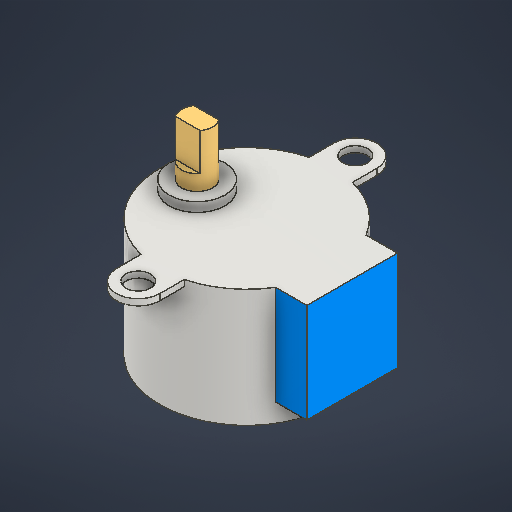
# Autodesk Inventor part: 28BJY-48
Saved by Autodesk Inventor 2026.2 (Build 302298010, 298A)
## iProperties
Created: 2026-05-01
Part Number: 28BJY-48
Material: 강철, 가공됨
Document SubType Name: Modeling
Designer: work
Density: 7.85 g/cm^3
Appearance: 강철
Author: work
Autodesk Inventor part; units mm, degrees
ref_plane "YZ Plane" through (0, 0, 0) normal (1, 0, 0) x (0, 1, 0)
ref_plane "XZ Plane" through (0, 0, 0) normal (0, 1, 0) x (-1, 0, 0)
ref_plane "XY Plane" through (0, 0, 0) normal (0, 0, 1) x (1, 0, 0)
sketch "스케치1" plane through (0, 0, 0) normal (0, 1, 0) x (-1, 0, 0)
  circle A0 centre (0, 0) radius 14
  line L0 (0, 7.3) -> (-17, 7.3)
  line L1 (-17, 7.3) -> (-17, -7.3)
  line L2 (-17, -7.3) -> (0, -7.3)
  line L3 (0, -7.3) -> (0, 7.3)
  point P0 (-11.9461, -7.3)
  point P1 (-11.9461, 7.3)
  dimension "d0" = 28
  dimension "d1" = 14.6
  dimension "d2" = 17
  constraints: 8 end point, 2 coincident, 2 parallel, 1 centre point, 1 horizontal, 1 midpoint, 1 perpendicular
  measures "d0" diameter of A0
  measures "d1" distance of L0.end L1.end
  measures "d2" distance of L1.end L2.end
extrude "돌출1" add sketch "스케치1" along normal blind 19
sketch "스케치2" plane through (0, 19, 0) normal (0, 1, 0) x (1, 0, 0)
  line L0 (0, 0) -> (-8, 0) construction
  circle A0 centre (-8, 0) radius 4.5
  line L1 (0, -17.5) -> (0, 17.5) construction
  line L2 (3.5, -17.5) -> (3.5, 17.5)
  line L3 (-3.5, 17.5) -> (-3.5, -17.5)
  arc A1 (-3.5, -17.5) -> (3.5, -17.5) centre (0, -17.5) ccw
  arc A2 (3.5, 17.5) -> (-3.5, 17.5) centre (0, 17.5) ccw
  circle A3 centre (0, 17.5) radius 2
  circle A4 centre (0, -17.5) radius 2
  line L4 (11.9461, -7.3) -> (17, -7.3) projected
  line L5 (17, -7.3) -> (17, 7.3) projected
  line L6 (17, 7.3) -> (11.9461, 7.3) projected
  arc A5 (11.9461, 7.3) -> (11.9461, -7.3) centre (0, 0) ccw projected
  point P0 (3.5, 13.5554)
  point P1 (3.5, -13.5554)
  point P2 (-3.5, 13.5554)
  point P3 (-3.5, -13.5554)
  dimension "d5" = 8
  dimension "d6" = 9
  dimension "d7" = 35
  dimension "d8" = 7
  dimension "d9" = 4
  dimension "d10" = 4
  constraints: 10 end point, 5 centre point, 4 point on circle, 4 tangent, 3 coincident, 1 horizontal, 1 midpoint, 1 parallel, 1 vertical
  measures "d5" distance of L0.start L0.end
  measures "d6" diameter of A0
  measures "d7" distance of L1.start L1.end
  measures "d8" distance between parallel lines of L3 L2
  measures "d9" diameter of A3
  measures "d10" diameter of A4
extrude "돌출2" add sketch "스케치2" against normal blind 1 contours L3 A2 L2 A5 | A5 L2 A1 L3 | A5 L6 L5 L4 L2
extrude "돌출3" add sketch "스케치2" along normal blind 1.5 contours A0
sketch "스케치3" plane through (-8, 20.5, 0) normal (0, 1, 0) x (1, 0, 0)
  circle A0 centre (0, 0) radius 2.5
  circle A1 centre (0, 0) radius 4.5 projected
  circle A2 centre (0, 0) radius 4.5 projected
  point P0 (8, 0)
  dimension "d15" = 5
  constraints: 1 centre point, 1 concentric
  measures "d15" diameter of A0
extrude "돌출4" add sketch "스케치3" along normal blind 2.5 contours A0
sketch "스케치4" plane through (-8, 23, 0) normal (0, 1, 0) x (1, 0, 0)
  circle A0 centre (0, 0) radius 2.5 projected
  line L0 (-2.5, 0) -> (2.5, 0) construction
  line L1 (-2, 1.5) -> (2, 1.5)
  line L2 (-2, -1.5) -> (2, -1.5)
  point P0 (8, 0)
  point P1 (0, -1.5)
  point P2 (0, 1.5)
  point P3 (-2, -1.5)
  dimension "d18" = 5
  dimension "d19" = 3
  constraints: 6 end point, 4 point on circle, 2 horizontal, 2 midpoint, 2 symmetric about line
  measures "d18" distance of L0.start L0.end
  measures "d19" distance of point (0, -1.5) point (0, 1.5)
extrude "돌출5" add sketch "스케치4" along normal blind 6 contours A0 L2 L1
sketch "스케치5" plane through (0, 0, 0) normal (0, -1, 0) x (1, 0, 0)
  line L0 (11.9461, 7.3) -> (17, 7.3) projected
  arc A0 (11.9461, 7.3) -> (11.9461, -7.3) centre (0, 0) ccw projected
  line L1 (17, -7.3) -> (11.9461, -7.3) projected
  line L2 (17, 7.3) -> (17, -7.3) projected
  circle A1 centre (0, 0) radius 14
  constraints: 1 coincident, 3 other
extrude "돌출6" cut sketch "스케치5" against normal blind 3 contours L0 L2 L1 A1
